Autodesk Fusion 360 part; units mm, degrees
(part 7 of 28)
  line L4044 (94.5774, 89.0483, -1.4859) -> (92.1274, 89.0483, -1.4859)
  line L4045 (92.1274, 89.0483, -1.4859) -> (92.1274, 92.0483, -1.4859)
  line L4046 (92.1274, 92.0483, -1.4859) -> (94.5774, 92.0483, -1.4859)
  line L4047 (94.5774, 92.0483, -1.4859) -> (94.5774, 89.0483, -1.4859)
  line L4048 (129.5024, 89.0483, -1.4859) -> (127.0524, 89.0483, -1.4859)
  line L4049 (127.0524, 89.0483, -1.4859) -> (127.0524, 92.0483, -1.4859)
  line L4050 (127.0524, 92.0483, -1.4859) -> (129.5024, 92.0483, -1.4859)
  line L4051 (129.5024, 92.0483, -1.4859) -> (129.5024, 89.0483, -1.4859)
  line L4052 (21.2483, 92.0145, -1.4859) -> (21.4312, 91.9551, -1.4859)
  line L4053 (21.4312, 91.9551, -1.4859) -> (21.6024, 91.8678, -1.4859)
  line L4054 (21.6024, 91.8678, -1.4859) -> (21.7579, 91.7548, -1.4859)
  line L4055 (21.7579, 91.7548, -1.4859) -> (21.8939, 91.6189, -1.4859)
  line L4056 (21.8939, 91.6189, -1.4859) -> (22.0069, 91.4634, -1.4859)
  line L4057 (22.0069, 91.4634, -1.4859) -> (22.0941, 91.2921, -1.4859)
  line L4058 (22.0941, 91.2921, -1.4859) -> (22.1535, 91.1093, -1.4859)
  line L4059 (22.1535, 91.1093, -1.4859) -> (22.1836, 90.9194, -1.4859)
  line L4060 (22.1836, 90.9194, -1.4859) -> (22.1874, 90.8233, -1.4859)
  line L4061 (22.1874, 90.8233, -1.4859) -> (22.1874, 90.2733, -1.4859)
  line L4062 (22.1874, 90.2733, -1.4859) -> (22.1836, 90.1772, -1.4859)
  line L4063 (22.1836, 90.1772, -1.4859) -> (22.1535, 89.9873, -1.4859)
  line L4064 (22.1535, 89.9873, -1.4859) -> (22.0941, 89.8045, -1.4859)
  line L4065 (22.0941, 89.8045, -1.4859) -> (22.0069, 89.6333, -1.4859)
  line L4066 (22.0069, 89.6333, -1.4859) -> (21.8939, 89.4777, -1.4859)
  line L4067 (21.8939, 89.4777, -1.4859) -> (21.7579, 89.3418, -1.4859)
  line L4068 (21.7579, 89.3418, -1.4859) -> (21.6024, 89.2288, -1.4859)
  line L4069 (21.6024, 89.2288, -1.4859) -> (21.4312, 89.1416, -1.4859)
  line L4070 (21.4312, 89.1416, -1.4859) -> (21.2483, 89.0822, -1.4859)
  line L4071 (21.2483, 89.0822, -1.4859) -> (21.0585, 89.0521, -1.4859)
  line L4072 (21.0585, 89.0521, -1.4859) -> (20.8663, 89.0521, -1.4859)
  line L4073 (20.8663, 89.0521, -1.4859) -> (20.6764, 89.0822, -1.4859)
  line L4074 (20.6764, 89.0822, -1.4859) -> (20.4936, 89.1416, -1.4859)
  line L4075 (20.4936, 89.1416, -1.4859) -> (20.3223, 89.2288, -1.4859)
  line L4076 (20.3223, 89.2288, -1.4859) -> (20.1668, 89.3418, -1.4859)
  line L4077 (20.1668, 89.3418, -1.4859) -> (20.0309, 89.4777, -1.4859)
  line L4078 (20.0309, 89.4777, -1.4859) -> (19.9179, 89.6333, -1.4859)
  line L4079 (19.9179, 89.6333, -1.4859) -> (19.8306, 89.8045, -1.4859)
  line L4080 (19.8306, 89.8045, -1.4859) -> (19.7712, 89.9873, -1.4859)
  line L4081 (19.7712, 89.9873, -1.4859) -> (19.7411, 90.1772, -1.4859)
  line L4082 (19.7411, 90.1772, -1.4859) -> (19.7374, 90.2733, -1.4859)
  line L4083 (19.7374, 90.2733, -1.4859) -> (19.7374, 90.8233, -1.4859)
  line L4084 (19.7374, 90.8233, -1.4859) -> (19.7411, 90.9194, -1.4859)
  line L4085 (19.7411, 90.9194, -1.4859) -> (19.7712, 91.1093, -1.4859)
  line L4086 (19.7712, 91.1093, -1.4859) -> (19.8306, 91.2921, -1.4859)
  line L4087 (19.8306, 91.2921, -1.4859) -> (19.9179, 91.4634, -1.4859)
  line L4088 (19.9179, 91.4634, -1.4859) -> (20.0309, 91.6189, -1.4859)
  line L4089 (20.0309, 91.6189, -1.4859) -> (20.1668, 91.7548, -1.4859)
  line L4090 (20.1668, 91.7548, -1.4859) -> (20.3223, 91.8678, -1.4859)
  line L4091 (20.3223, 91.8678, -1.4859) -> (20.4936, 91.9551, -1.4859)
  line L4092 (20.4936, 91.9551, -1.4859) -> (20.6764, 92.0145, -1.4859)
  line L4093 (20.6764, 92.0145, -1.4859) -> (20.8663, 92.0445, -1.4859)
  line L4094 (20.8663, 92.0445, -1.4859) -> (21.0585, 92.0445, -1.4859)
  line L4095 (21.0585, 92.0445, -1.4859) -> (21.2483, 92.0145, -1.4859)
  line L4096 (56.1733, 92.0145, -1.4859) -> (56.3562, 91.9551, -1.4859)
  line L4097 (56.3562, 91.9551, -1.4859) -> (56.5274, 91.8678, -1.4859)
  line L4098 (56.5274, 91.8678, -1.4859) -> (56.6829, 91.7548, -1.4859)
  line L4099 (56.6829, 91.7548, -1.4859) -> (56.8189, 91.6189, -1.4859)
  line L4100 (56.8189, 91.6189, -1.4859) -> (56.9319, 91.4634, -1.4859)
  line L4101 (56.9319, 91.4634, -1.4859) -> (57.0191, 91.2921, -1.4859)
  line L4102 (57.0191, 91.2921, -1.4859) -> (57.0785, 91.1093, -1.4859)
  line L4103 (57.0785, 91.1093, -1.4859) -> (57.1086, 90.9194, -1.4859)
  line L4104 (57.1086, 90.9194, -1.4859) -> (57.1124, 90.8233, -1.4859)
  line L4105 (57.1124, 90.8233, -1.4859) -> (57.1124, 90.2733, -1.4859)
  line L4106 (57.1124, 90.2733, -1.4859) -> (57.1086, 90.1772, -1.4859)
  line L4107 (57.1086, 90.1772, -1.4859) -> (57.0785, 89.9873, -1.4859)
  line L4108 (57.0785, 89.9873, -1.4859) -> (57.0191, 89.8045, -1.4859)
  line L4109 (57.0191, 89.8045, -1.4859) -> (56.9319, 89.6333, -1.4859)
  line L4110 (56.9319, 89.6333, -1.4859) -> (56.8189, 89.4777, -1.4859)
  line L4111 (56.8189, 89.4777, -1.4859) -> (56.6829, 89.3418, -1.4859)
  line L4112 (56.6829, 89.3418, -1.4859) -> (56.5274, 89.2288, -1.4859)
  line L4113 (56.5274, 89.2288, -1.4859) -> (56.3562, 89.1416, -1.4859)
  line L4114 (56.3562, 89.1416, -1.4859) -> (56.1733, 89.0822, -1.4859)
  line L4115 (56.1733, 89.0822, -1.4859) -> (55.9835, 89.0521, -1.4859)
  line L4116 (55.9835, 89.0521, -1.4859) -> (55.7913, 89.0521, -1.4859)
  line L4117 (55.7913, 89.0521, -1.4859) -> (55.6014, 89.0822, -1.4859)
  line L4118 (55.6014, 89.0822, -1.4859) -> (55.4186, 89.1416, -1.4859)
  line L4119 (55.4186, 89.1416, -1.4859) -> (55.2473, 89.2288, -1.4859)
  line L4120 (55.2473, 89.2288, -1.4859) -> (55.0918, 89.3418, -1.4859)
  line L4121 (55.0918, 89.3418, -1.4859) -> (54.9559, 89.4777, -1.4859)
  line L4122 (54.9559, 89.4777, -1.4859) -> (54.8429, 89.6333, -1.4859)
  line L4123 (54.8429, 89.6333, -1.4859) -> (54.7556, 89.8045, -1.4859)
  line L4124 (54.7556, 89.8045, -1.4859) -> (54.6962, 89.9873, -1.4859)
  line L4125 (54.6962, 89.9873, -1.4859) -> (54.6661, 90.1772, -1.4859)
  line L4126 (54.6661, 90.1772, -1.4859) -> (54.6624, 90.2733, -1.4859)
  line L4127 (54.6624, 90.2733, -1.4859) -> (54.6624, 90.8233, -1.4859)
  line L4128 (54.6624, 90.8233, -1.4859) -> (54.6661, 90.9194, -1.4859)
  line L4129 (54.6661, 90.9194, -1.4859) -> (54.6962, 91.1093, -1.4859)
  line L4130 (54.6962, 91.1093, -1.4859) -> (54.7556, 91.2921, -1.4859)
  line L4131 (54.7556, 91.2921, -1.4859) -> (54.8429, 91.4634, -1.4859)
  line L4132 (54.8429, 91.4634, -1.4859) -> (54.9559, 91.6189, -1.4859)
  line L4133 (54.9559, 91.6189, -1.4859) -> (55.0918, 91.7548, -1.4859)
  line L4134 (55.0918, 91.7548, -1.4859) -> (55.2473, 91.8678, -1.4859)
  line L4135 (55.2473, 91.8678, -1.4859) -> (55.4186, 91.9551, -1.4859)
  line L4136 (55.4186, 91.9551, -1.4859) -> (55.6014, 92.0145, -1.4859)
  line L4137 (55.6014, 92.0145, -1.4859) -> (55.7913, 92.0445, -1.4859)
  line L4138 (55.7913, 92.0445, -1.4859) -> (55.9835, 92.0445, -1.4859)
  line L4139 (55.9835, 92.0445, -1.4859) -> (56.1733, 92.0145, -1.4859)
  line L4140 (91.0983, 92.0145, -1.4859) -> (91.2812, 91.9551, -1.4859)
  line L4141 (91.2812, 91.9551, -1.4859) -> (91.4524, 91.8678, -1.4859)
  line L4142 (91.4524, 91.8678, -1.4859) -> (91.6079, 91.7548, -1.4859)
  line L4143 (91.6079, 91.7548, -1.4859) -> (91.7439, 91.6189, -1.4859)
  line L4144 (91.7439, 91.6189, -1.4859) -> (91.8569, 91.4634, -1.4859)
  line L4145 (91.8569, 91.4634, -1.4859) -> (91.9441, 91.2921, -1.4859)
  line L4146 (91.9441, 91.2921, -1.4859) -> (92.0035, 91.1093, -1.4859)
  line L4147 (92.0035, 91.1093, -1.4859) -> (92.0336, 90.9194, -1.4859)
  line L4148 (92.0336, 90.9194, -1.4859) -> (92.0374, 90.8233, -1.4859)
  line L4149 (92.0374, 90.8233, -1.4859) -> (92.0374, 90.2733, -1.4859)
  line L4150 (92.0374, 90.2733, -1.4859) -> (92.0336, 90.1772, -1.4859)
  line L4151 (92.0336, 90.1772, -1.4859) -> (92.0035, 89.9873, -1.4859)
  line L4152 (92.0035, 89.9873, -1.4859) -> (91.9441, 89.8045, -1.4859)
  line L4153 (91.9441, 89.8045, -1.4859) -> (91.8569, 89.6333, -1.4859)
  line L4154 (91.8569, 89.6333, -1.4859) -> (91.7439, 89.4777, -1.4859)
  line L4155 (91.7439, 89.4777, -1.4859) -> (91.6079, 89.3418, -1.4859)
  line L4156 (91.6079, 89.3418, -1.4859) -> (91.4524, 89.2288, -1.4859)
  line L4157 (91.4524, 89.2288, -1.4859) -> (91.2812, 89.1416, -1.4859)
  line L4158 (91.2812, 89.1416, -1.4859) -> (91.0983, 89.0822, -1.4859)
  line L4159 (91.0983, 89.0822, -1.4859) -> (90.9085, 89.0521, -1.4859)
  line L4160 (90.9085, 89.0521, -1.4859) -> (90.7163, 89.0521, -1.4859)
  line L4161 (90.7163, 89.0521, -1.4859) -> (90.5264, 89.0822, -1.4859)
  line L4162 (90.5264, 89.0822, -1.4859) -> (90.3436, 89.1416, -1.4859)
  line L4163 (90.3436, 89.1416, -1.4859) -> (90.1723, 89.2288, -1.4859)
  line L4164 (90.1723, 89.2288, -1.4859) -> (90.0168, 89.3418, -1.4859)
  line L4165 (90.0168, 89.3418, -1.4859) -> (89.8809, 89.4777, -1.4859)
  line L4166 (89.8809, 89.4777, -1.4859) -> (89.7679, 89.6333, -1.4859)
  line L4167 (89.7679, 89.6333, -1.4859) -> (89.6806, 89.8045, -1.4859)
  line L4168 (89.6806, 89.8045, -1.4859) -> (89.6212, 89.9873, -1.4859)
  line L4169 (89.6212, 89.9873, -1.4859) -> (89.5911, 90.1772, -1.4859)
  line L4170 (89.5911, 90.1772, -1.4859) -> (89.5874, 90.2733, -1.4859)
  line L4171 (89.5874, 90.2733, -1.4859) -> (89.5874, 90.8233, -1.4859)
  line L4172 (89.5874, 90.8233, -1.4859) -> (89.5911, 90.9194, -1.4859)
  line L4173 (89.5911, 90.9194, -1.4859) -> (89.6212, 91.1093, -1.4859)
  line L4174 (89.6212, 91.1093, -1.4859) -> (89.6806, 91.2921, -1.4859)
  line L4175 (89.6806, 91.2921, -1.4859) -> (89.7679, 91.4634, -1.4859)
  line L4176 (89.7679, 91.4634, -1.4859) -> (89.8809, 91.6189, -1.4859)
  line L4177 (89.8809, 91.6189, -1.4859) -> (90.0168, 91.7548, -1.4859)
  line L4178 (90.0168, 91.7548, -1.4859) -> (90.1723, 91.8678, -1.4859)
  line L4179 (90.1723, 91.8678, -1.4859) -> (90.3436, 91.9551, -1.4859)
  line L4180 (90.3436, 91.9551, -1.4859) -> (90.5264, 92.0145, -1.4859)
  line L4181 (90.5264, 92.0145, -1.4859) -> (90.7163, 92.0445, -1.4859)
  line L4182 (90.7163, 92.0445, -1.4859) -> (90.9085, 92.0445, -1.4859)
  line L4183 (90.9085, 92.0445, -1.4859) -> (91.0983, 92.0145, -1.4859)
  line L4184 (126.0233, 92.0145, -1.4859) -> (126.2062, 91.9551, -1.4859)
  line L4185 (126.2062, 91.9551, -1.4859) -> (126.3774, 91.8678, -1.4859)
  line L4186 (126.3774, 91.8678, -1.4859) -> (126.5329, 91.7548, -1.4859)
  line L4187 (126.5329, 91.7548, -1.4859) -> (126.6689, 91.6189, -1.4859)
  line L4188 (126.6689, 91.6189, -1.4859) -> (126.7819, 91.4634, -1.4859)
  line L4189 (126.7819, 91.4634, -1.4859) -> (126.8691, 91.2921, -1.4859)
  line L4190 (126.8691, 91.2921, -1.4859) -> (126.9285, 91.1093, -1.4859)
  line L4191 (126.9285, 91.1093, -1.4859) -> (126.9586, 90.9194, -1.4859)
  line L4192 (126.9586, 90.9194, -1.4859) -> (126.9624, 90.8233, -1.4859)
  line L4193 (126.9624, 90.8233, -1.4859) -> (126.9624, 90.2733, -1.4859)
  line L4194 (126.9624, 90.2733, -1.4859) -> (126.9586, 90.1772, -1.4859)
  line L4195 (126.9586, 90.1772, -1.4859) -> (126.9285, 89.9873, -1.4859)
  line L4196 (126.9285, 89.9873, -1.4859) -> (126.8691, 89.8045, -1.4859)
  line L4197 (126.8691, 89.8045, -1.4859) -> (126.7819, 89.6333, -1.4859)
  line L4198 (126.7819, 89.6333, -1.4859) -> (126.6689, 89.4777, -1.4859)
  line L4199 (126.6689, 89.4777, -1.4859) -> (126.5329, 89.3418, -1.4859)
  line L4200 (126.5329, 89.3418, -1.4859) -> (126.3774, 89.2288, -1.4859)
  line L4201 (126.3774, 89.2288, -1.4859) -> (126.2062, 89.1416, -1.4859)
  line L4202 (126.2062, 89.1416, -1.4859) -> (126.0233, 89.0822, -1.4859)
  line L4203 (126.0233, 89.0822, -1.4859) -> (125.8335, 89.0521, -1.4859)
  line L4204 (125.8335, 89.0521, -1.4859) -> (125.6413, 89.0521, -1.4859)
  line L4205 (125.6413, 89.0521, -1.4859) -> (125.4514, 89.0822, -1.4859)
  line L4206 (125.4514, 89.0822, -1.4859) -> (125.2686, 89.1416, -1.4859)
  line L4207 (125.2686, 89.1416, -1.4859) -> (125.0973, 89.2288, -1.4859)
  line L4208 (125.0973, 89.2288, -1.4859) -> (124.9418, 89.3418, -1.4859)
  line L4209 (124.9418, 89.3418, -1.4859) -> (124.8059, 89.4777, -1.4859)
  line L4210 (124.8059, 89.4777, -1.4859) -> (124.6929, 89.6333, -1.4859)
  line L4211 (124.6929, 89.6333, -1.4859) -> (124.6056, 89.8045, -1.4859)
  line L4212 (124.6056, 89.8045, -1.4859) -> (124.5462, 89.9873, -1.4859)
  line L4213 (124.5462, 89.9873, -1.4859) -> (124.5161, 90.1772, -1.4859)
  line L4214 (124.5161, 90.1772, -1.4859) -> (124.5124, 90.2733, -1.4859)
  line L4215 (124.5124, 90.2733, -1.4859) -> (124.5124, 90.8233, -1.4859)
  line L4216 (124.5124, 90.8233, -1.4859) -> (124.5161, 90.9194, -1.4859)
  line L4217 (124.5161, 90.9194, -1.4859) -> (124.5462, 91.1093, -1.4859)
  line L4218 (124.5462, 91.1093, -1.4859) -> (124.6056, 91.2921, -1.4859)
  line L4219 (124.6056, 91.2921, -1.4859) -> (124.6929, 91.4634, -1.4859)
  line L4220 (124.6929, 91.4634, -1.4859) -> (124.8059, 91.6189, -1.4859)
  line L4221 (124.8059, 91.6189, -1.4859) -> (124.9418, 91.7548, -1.4859)
  line L4222 (124.9418, 91.7548, -1.4859) -> (125.0973, 91.8678, -1.4859)
  line L4223 (125.0973, 91.8678, -1.4859) -> (125.2686, 91.9551, -1.4859)
  line L4224 (125.2686, 91.9551, -1.4859) -> (125.4514, 92.0145, -1.4859)
  line L4225 (125.4514, 92.0145, -1.4859) -> (125.6413, 92.0445, -1.4859)
  line L4226 (125.6413, 92.0445, -1.4859) -> (125.8335, 92.0445, -1.4859)
  line L4227 (125.8335, 92.0445, -1.4859) -> (126.0233, 92.0145, -1.4859)
  line L4228 (33.8345, 93.498, -1.4859) -> (34.021, 93.4374, -1.4859)
  line L4229 (34.021, 93.4374, -1.4859) -> (34.1958, 93.3483, -1.4859)
  line L4230 (34.1958, 93.3483, -1.4859) -> (34.3545, 93.233, -1.4859)
  line L4231 (34.3545, 93.233, -1.4859) -> (34.4932, 93.0943, -1.4859)
  line L4232 (34.4932, 93.0943, -1.4859) -> (34.6085, 92.9357, -1.4859)
  line L4233 (34.6085, 92.9357, -1.4859) -> (34.6975, 92.7609, -1.4859)
  line L4234 (34.6975, 92.7609, -1.4859) -> (34.7582, 92.5743, -1.4859)
  line L4235 (34.7582, 92.5743, -1.4859) -> (34.7888, 92.3806, -1.4859)
  line L4236 (34.7888, 92.3806, -1.4859) -> (34.7927, 92.2825, -1.4859)
  line L4237 (34.7927, 92.2825, -1.4859) -> (34.7927, 91.7825, -1.4859)
  line L4238 (34.7927, 91.7825, -1.4859) -> (34.7888, 91.6845, -1.4859)
  line L4239 (34.7888, 91.6845, -1.4859) -> (34.7582, 91.4907, -1.4859)
  line L4240 (34.7582, 91.4907, -1.4859) -> (34.6975, 91.3042, -1.4859)
  line L4241 (34.6975, 91.3042, -1.4859) -> (34.6085, 91.1294, -1.4859)
  line L4242 (34.6085, 91.1294, -1.4859) -> (34.4932, 90.9707, -1.4859)
  line L4243 (34.4932, 90.9707, -1.4859) -> (34.3545, 90.832, -1.4859)
  line L4244 (34.3545, 90.832, -1.4859) -> (34.1958, 90.7167, -1.4859)
  line L4245 (34.1958, 90.7167, -1.4859) -> (34.021, 90.6277, -1.4859)
  line L4246 (34.021, 90.6277, -1.4859) -> (33.8345, 90.5671, -1.4859)
  line L4247 (33.8345, 90.5671, -1.4859) -> (33.6408, 90.5364, -1.4859)
  line L4248 (33.6408, 90.5364, -1.4859) -> (33.4446, 90.5364, -1.4859)
  line L4249 (33.4446, 90.5364, -1.4859) -> (33.2509, 90.5671, -1.4859)
  line L4250 (33.2509, 90.5671, -1.4859) -> (33.0643, 90.6277, -1.4859)
  line L4251 (33.0643, 90.6277, -1.4859) -> (32.8896, 90.7167, -1.4859)
  line L4252 (32.8896, 90.7167, -1.4859) -> (32.7309, 90.832, -1.4859)
  line L4253 (32.7309, 90.832, -1.4859) -> (32.5922, 90.9707, -1.4859)
  line L4254 (32.5922, 90.9707, -1.4859) -> (32.4769, 91.1294, -1.4859)
  line L4255 (32.4769, 91.1294, -1.4859) -> (32.3878, 91.3042, -1.4859)
  line L4256 (32.3878, 91.3042, -1.4859) -> (32.3272, 91.4907, -1.4859)
  line L4257 (32.3272, 91.4907, -1.4859) -> (32.2965, 91.6845, -1.4859)
  line L4258 (32.2965, 91.6845, -1.4859) -> (32.2927, 91.7825, -1.4859)
  line L4259 (32.2927, 91.7825, -1.4859) -> (32.2927, 92.2825, -1.4859)
  line L4260 (32.2927, 92.2825, -1.4859) -> (32.2965, 92.3806, -1.4859)
  line L4261 (32.2965, 92.3806, -1.4859) -> (32.3272, 92.5743, -1.4859)
  line L4262 (32.3272, 92.5743, -1.4859) -> (32.3878, 92.7609, -1.4859)
  line L4263 (32.3878, 92.7609, -1.4859) -> (32.4769, 92.9357, -1.4859)
  line L4264 (32.4769, 92.9357, -1.4859) -> (32.5922, 93.0943, -1.4859)
  line L4265 (32.5922, 93.0943, -1.4859) -> (32.7309, 93.233, -1.4859)
  line L4266 (32.7309, 93.233, -1.4859) -> (32.8896, 93.3483, -1.4859)
  line L4267 (32.8896, 93.3483, -1.4859) -> (33.0643, 93.4374, -1.4859)
  line L4268 (33.0643, 93.4374, -1.4859) -> (33.2509, 93.498, -1.4859)
  line L4269 (33.2509, 93.498, -1.4859) -> (33.4446, 93.5287, -1.4859)
  line L4270 (33.4446, 93.5287, -1.4859) -> (33.6408, 93.5287, -1.4859)
  line L4271 (33.6408, 93.5287, -1.4859) -> (33.8345, 93.498, -1.4859)
  line L4272 (68.7595, 93.498, -1.4859) -> (68.946, 93.4374, -1.4859)
  line L4273 (68.946, 93.4374, -1.4859) -> (69.1208, 93.3483, -1.4859)
  line L4274 (69.1208, 93.3483, -1.4859) -> (69.2795, 93.233, -1.4859)
  line L4275 (69.2795, 93.233, -1.4859) -> (69.4182, 93.0943, -1.4859)
  line L4276 (69.4182, 93.0943, -1.4859) -> (69.5335, 92.9357, -1.4859)
  line L4277 (69.5335, 92.9357, -1.4859) -> (69.6225, 92.7609, -1.4859)
  line L4278 (69.6225, 92.7609, -1.4859) -> (69.6832, 92.5743, -1.4859)
  line L4279 (69.6832, 92.5743, -1.4859) -> (69.7138, 92.3806, -1.4859)
  line L4280 (69.7138, 92.3806, -1.4859) -> (69.7177, 92.2825, -1.4859)
  line L4281 (69.7177, 92.2825, -1.4859) -> (69.7177, 91.7825, -1.4859)
  line L4282 (69.7177, 91.7825, -1.4859) -> (69.7138, 91.6845, -1.4859)
  line L4283 (69.7138, 91.6845, -1.4859) -> (69.6832, 91.4907, -1.4859)
  line L4284 (69.6832, 91.4907, -1.4859) -> (69.6225, 91.3042, -1.4859)
  line L4285 (69.6225, 91.3042, -1.4859) -> (69.5335, 91.1294, -1.4859)
  line L4286 (69.5335, 91.1294, -1.4859) -> (69.4182, 90.9707, -1.4859)
  line L4287 (69.4182, 90.9707, -1.4859) -> (69.2795, 90.832, -1.4859)
  line L4288 (69.2795, 90.832, -1.4859) -> (69.1208, 90.7167, -1.4859)
  line L4289 (69.1208, 90.7167, -1.4859) -> (68.946, 90.6277, -1.4859)
  line L4290 (68.946, 90.6277, -1.4859) -> (68.7595, 90.5671, -1.4859)
  line L4291 (68.7595, 90.5671, -1.4859) -> (68.5658, 90.5364, -1.4859)
  line L4292 (68.5658, 90.5364, -1.4859) -> (68.3696, 90.5364, -1.4859)
  line L4293 (68.3696, 90.5364, -1.4859) -> (68.1759, 90.5671, -1.4859)
  line L4294 (68.1759, 90.5671, -1.4859) -> (67.9893, 90.6277, -1.4859)
  line L4295 (67.9893, 90.6277, -1.4859) -> (67.8146, 90.7167, -1.4859)
  line L4296 (67.8146, 90.7167, -1.4859) -> (67.6559, 90.832, -1.4859)
  line L4297 (67.6559, 90.832, -1.4859) -> (67.5172, 90.9707, -1.4859)
  line L4298 (67.5172, 90.9707, -1.4859) -> (67.4019, 91.1294, -1.4859)
  line L4299 (67.4019, 91.1294, -1.4859) -> (67.3128, 91.3042, -1.4859)
  line L4300 (67.3128, 91.3042, -1.4859) -> (67.2522, 91.4907, -1.4859)
  line L4301 (67.2522, 91.4907, -1.4859) -> (67.2215, 91.6845, -1.4859)
  line L4302 (67.2215, 91.6845, -1.4859) -> (67.2177, 91.7825, -1.4859)
  line L4303 (67.2177, 91.7825, -1.4859) -> (67.2177, 92.2825, -1.4859)
  line L4304 (67.2177, 92.2825, -1.4859) -> (67.2215, 92.3806, -1.4859)
  line L4305 (67.2215, 92.3806, -1.4859) -> (67.2522, 92.5743, -1.4859)
  line L4306 (67.2522, 92.5743, -1.4859) -> (67.3128, 92.7609, -1.4859)
  line L4307 (67.3128, 92.7609, -1.4859) -> (67.4019, 92.9357, -1.4859)
  line L4308 (67.4019, 92.9357, -1.4859) -> (67.5172, 93.0943, -1.4859)
  line L4309 (67.5172, 93.0943, -1.4859) -> (67.6559, 93.233, -1.4859)
  line L4310 (67.6559, 93.233, -1.4859) -> (67.8146, 93.3483, -1.4859)
  line L4311 (67.8146, 93.3483, -1.4859) -> (67.9893, 93.4374, -1.4859)
  line L4312 (67.9893, 93.4374, -1.4859) -> (68.1759, 93.498, -1.4859)
  line L4313 (68.1759, 93.498, -1.4859) -> (68.3696, 93.5287, -1.4859)
  line L4314 (68.3696, 93.5287, -1.4859) -> (68.5658, 93.5287, -1.4859)
  line L4315 (68.5658, 93.5287, -1.4859) -> (68.7595, 93.498, -1.4859)
  line L4316 (103.6845, 93.498, -1.4859) -> (103.871, 93.4374, -1.4859)
  line L4317 (103.871, 93.4374, -1.4859) -> (104.0458, 93.3483, -1.4859)
  line L4318 (104.0458, 93.3483, -1.4859) -> (104.2045, 93.233, -1.4859)
  line L4319 (104.2045, 93.233, -1.4859) -> (104.3432, 93.0943, -1.4859)
  line L4320 (104.3432, 93.0943, -1.4859) -> (104.4585, 92.9357, -1.4859)
  line L4321 (104.4585, 92.9357, -1.4859) -> (104.5475, 92.7609, -1.4859)
  line L4322 (104.5475, 92.7609, -1.4859) -> (104.6082, 92.5743, -1.4859)
  line L4323 (104.6082, 92.5743, -1.4859) -> (104.6388, 92.3806, -1.4859)
  line L4324 (104.6388, 92.3806, -1.4859) -> (104.6427, 92.2825, -1.4859)
  line L4325 (104.6427, 92.2825, -1.4859) -> (104.6427, 91.7825, -1.4859)
  line L4326 (104.6427, 91.7825, -1.4859) -> (104.6388, 91.6845, -1.4859)
  line L4327 (104.6388, 91.6845, -1.4859) -> (104.6082, 91.4907, -1.4859)
  line L4328 (104.6082, 91.4907, -1.4859) -> (104.5475, 91.3042, -1.4859)
  line L4329 (104.5475, 91.3042, -1.4859) -> (104.4585, 91.1294, -1.4859)
  line L4330 (104.4585, 91.1294, -1.4859) -> (104.3432, 90.9707, -1.4859)
  line L4331 (104.3432, 90.9707, -1.4859) -> (104.2045, 90.832, -1.4859)
  line L4332 (104.2045, 90.832, -1.4859) -> (104.0458, 90.7167, -1.4859)
  line L4333 (104.0458, 90.7167, -1.4859) -> (103.871, 90.6277, -1.4859)
  line L4334 (103.871, 90.6277, -1.4859) -> (103.6845, 90.5671, -1.4859)
  line L4335 (103.6845, 90.5671, -1.4859) -> (103.4908, 90.5364, -1.4859)
  line L4336 (103.4908, 90.5364, -1.4859) -> (103.2946, 90.5364, -1.4859)
  line L4337 (103.2946, 90.5364, -1.4859) -> (103.1009, 90.5671, -1.4859)
  line L4338 (103.1009, 90.5671, -1.4859) -> (102.9143, 90.6277, -1.4859)
  line L4339 (102.9143, 90.6277, -1.4859) -> (102.7396, 90.7167, -1.4859)
  line L4340 (102.7396, 90.7167, -1.4859) -> (102.5809, 90.832, -1.4859)
  line L4341 (102.5809, 90.832, -1.4859) -> (102.4422, 90.9707, -1.4859)
  line L4342 (102.4422, 90.9707, -1.4859) -> (102.3269, 91.1294, -1.4859)
  line L4343 (102.3269, 91.1294, -1.4859) -> (102.2378, 91.3042, -1.4859)
  line L4344 (102.2378, 91.3042, -1.4859) -> (102.1772, 91.4907, -1.4859)
  line L4345 (102.1772, 91.4907, -1.4859) -> (102.1465, 91.6845, -1.4859)
  line L4346 (102.1465, 91.6845, -1.4859) -> (102.1427, 91.7825, -1.4859)
  line L4347 (102.1427, 91.7825, -1.4859) -> (102.1427, 92.2825, -1.4859)
  line L4348 (102.1427, 92.2825, -1.4859) -> (102.1465, 92.3806, -1.4859)
  line L4349 (102.1465, 92.3806, -1.4859) -> (102.1772, 92.5743, -1.4859)
  line L4350 (102.1772, 92.5743, -1.4859) -> (102.2378, 92.7609, -1.4859)
  line L4351 (102.2378, 92.7609, -1.4859) -> (102.3269, 92.9357, -1.4859)
  line L4352 (102.3269, 92.9357, -1.4859) -> (102.4422, 93.0943, -1.4859)
  line L4353 (102.4422, 93.0943, -1.4859) -> (102.5809, 93.233, -1.4859)
  line L4354 (102.5809, 93.233, -1.4859) -> (102.7396, 93.3483, -1.4859)
  line L4355 (102.7396, 93.3483, -1.4859) -> (102.9143, 93.4374, -1.4859)
  line L4356 (102.9143, 93.4374, -1.4859) -> (103.1009, 93.498, -1.4859)
  line L4357 (103.1009, 93.498, -1.4859) -> (103.2946, 93.5287, -1.4859)
  line L4358 (103.2946, 93.5287, -1.4859) -> (103.4908, 93.5287, -1.4859)
  line L4359 (103.4908, 93.5287, -1.4859) -> (103.6845, 93.498, -1.4859)
  line L4360 (138.6095, 93.498, -1.4859) -> (138.796, 93.4374, -1.4859)
  line L4361 (138.796, 93.4374, -1.4859) -> (138.9708, 93.3483, -1.4859)
  line L4362 (138.9708, 93.3483, -1.4859) -> (139.1295, 93.233, -1.4859)
  line L4363 (139.1295, 93.233, -1.4859) -> (139.2682, 93.0943, -1.4859)
  line L4364 (139.2682, 93.0943, -1.4859) -> (139.3835, 92.9357, -1.4859)
  line L4365 (139.3835, 92.9357, -1.4859) -> (139.4725, 92.7609, -1.4859)
  line L4366 (139.4725, 92.7609, -1.4859) -> (139.5332, 92.5743, -1.4859)
  line L4367 (139.5332, 92.5743, -1.4859) -> (139.5638, 92.3806, -1.4859)
  line L4368 (139.5638, 92.3806, -1.4859) -> (139.5677, 92.2825, -1.4859)
  line L4369 (139.5677, 92.2825, -1.4859) -> (139.5677, 91.7825, -1.4859)
  line L4370 (139.5677, 91.7825, -1.4859) -> (139.5638, 91.6845, -1.4859)
  line L4371 (139.5638, 91.6845, -1.4859) -> (139.5332, 91.4907, -1.4859)
  line L4372 (139.5332, 91.4907, -1.4859) -> (139.4725, 91.3042, -1.4859)
  line L4373 (139.4725, 91.3042, -1.4859) -> (139.3835, 91.1294, -1.4859)
  line L4374 (139.3835, 91.1294, -1.4859) -> (139.2682, 90.9707, -1.4859)
  line L4375 (139.2682, 90.9707, -1.4859) -> (139.1295, 90.832, -1.4859)
  line L4376 (139.1295, 90.832, -1.4859) -> (138.9708, 90.7167, -1.4859)
  line L4377 (138.9708, 90.7167, -1.4859) -> (138.796, 90.6277, -1.4859)
  line L4378 (138.796, 90.6277, -1.4859) -> (138.6095, 90.5671, -1.4859)
  line L4379 (138.6095, 90.5671, -1.4859) -> (138.4158, 90.5364, -1.4859)
  line L4380 (138.4158, 90.5364, -1.4859) -> (138.2196, 90.5364, -1.4859)
  line L4381 (138.2196, 90.5364, -1.4859) -> (138.0259, 90.5671, -1.4859)
  line L4382 (138.0259, 90.5671, -1.4859) -> (137.8393, 90.6277, -1.4859)
  line L4383 (137.8393, 90.6277, -1.4859) -> (137.6646, 90.7167, -1.4859)
  line L4384 (137.6646, 90.7167, -1.4859) -> (137.5059, 90.832, -1.4859)
  line L4385 (137.5059, 90.832, -1.4859) -> (137.3672, 90.9707, -1.4859)
  line L4386 (137.3672, 90.9707, -1.4859) -> (137.2519, 91.1294, -1.4859)
  line L4387 (137.2519, 91.1294, -1.4859) -> (137.1628, 91.3042, -1.4859)
  line L4388 (137.1628, 91.3042, -1.4859) -> (137.1022, 91.4907, -1.4859)
  line L4389 (137.1022, 91.4907, -1.4859) -> (137.0715, 91.6845, -1.4859)
  line L4390 (137.0715, 91.6845, -1.4859) -> (137.0677, 91.7825, -1.4859)
  line L4391 (137.0677, 91.7825, -1.4859) -> (137.0677, 92.2825, -1.4859)
  line L4392 (137.0677, 92.2825, -1.4859) -> (137.0715, 92.3806, -1.4859)
  line L4393 (137.0715, 92.3806, -1.4859) -> (137.1022, 92.5743, -1.4859)
  line L4394 (137.1022, 92.5743, -1.4859) -> (137.1628, 92.7609, -1.4859)
  line L4395 (137.1628, 92.7609, -1.4859) -> (137.2519, 92.9357, -1.4859)
  line L4396 (137.2519, 92.9357, -1.4859) -> (137.3672, 93.0943, -1.4859)
  line L4397 (137.3672, 93.0943, -1.4859) -> (137.5059, 93.233, -1.4859)
  line L4398 (137.5059, 93.233, -1.4859) -> (137.6646, 93.3483, -1.4859)
  line L4399 (137.6646, 93.3483, -1.4859) -> (137.8393, 93.4374, -1.4859)
  line L4400 (137.8393, 93.4374, -1.4859) -> (138.0259, 93.498, -1.4859)
  line L4401 (138.0259, 93.498, -1.4859) -> (138.2196, 93.5287, -1.4859)
  line L4402 (138.2196, 93.5287, -1.4859) -> (138.4158, 93.5287, -1.4859)
  line L4403 (138.4158, 93.5287, -1.4859) -> (138.6095, 93.498, -1.4859)
  line L4404 (0.0231, 6.9946) -> (0.025, 6.985)
  line L4405 (0.025, 6.985) -> (0.025, 0.025)
  line L4406 (0.025, 0.025) -> (7.62, 0.025)
  line L4407 (7.62, 0.025) -> (7.6296, 0.0231)
  line L4408 (7.6296, 0.0231) -> (7.6431, 0.0096)
  line L4409 (7.6431, 0.0096) -> (7.6431, -0.0096)
  line L4410 (7.6431, -0.0096) -> (7.6296, -0.0231)
  line L4411 (7.6296, -0.0231) -> (7.62, -0.025)
  line L4412 (7.62, -0.025) -> (0.025, -0.025)
  line L4413 (0.025, -0.025) -> (0.025, -5.08)
  line L4414 (0.025, -5.08) -> (0.0231, -5.0896)
  line L4415 (0.0231, -5.0896) -> (0.0096, -5.1031)
  line L4416 (0.0096, -5.1031) -> (-0.0096, -5.1031)
  line L4417 (-0.0096, -5.1031) -> (-0.0231, -5.0896)
  line L4418 (-0.0231, -5.0896) -> (-0.025, -5.08)
  line L4419 (-0.025, -5.08) -> (-0.025, -0.025)
  line L4420 (-0.025, -0.025) -> (-5.08, -0.025)
  line L4421 (-5.08, -0.025) -> (-5.0896, -0.0231)
  line L4422 (-5.0896, -0.0231) -> (-5.1031, -0.0096)
  line L4423 (-5.1031, -0.0096) -> (-5.1031, 0.0096)
  line L4424 (-5.1031, 0.0096) -> (-5.0896, 0.0231)
  line L4425 (-5.0896, 0.0231) -> (-5.08, 0.025)
  line L4426 (-5.08, 0.025) -> (-0.025, 0.025)
  line L4427 (-0.025, 0.025) -> (-0.025, 6.985)
  line L4428 (-0.025, 6.985) -> (-0.0231, 6.9946)
  line L4429 (-0.0231, 6.9946) -> (-0.0096, 7.0081)
  line L4430 (-0.0096, 7.0081) -> (0.0096, 7.0081)
  line L4431 (0.0096, 7.0081) -> (0.0231, 6.9946)
  line L4432 (66.015, 36.83, -1.4859) -> (66.0246, 36.8281, -1.4859)
  line L4433 (66.0246, 36.8281, -1.4859) -> (66.0381, 36.8146, -1.4859)
  line L4434 (66.0381, 36.8146, -1.4859) -> (66.04, 36.805, -1.4859)
  line L4435 (66.04, 36.805, -1.4859) -> (66.04, 5.055, -1.4859)
  line L4436 (66.04, 5.055, -1.4859) -> (66.0381, 5.0454, -1.4859)
  line L4437 (66.0381, 5.0454, -1.4859) -> (66.0246, 5.0319, -1.4859)
  line L4438 (66.0246, 5.0319, -1.4859) -> (66.015, 5.03, -1.4859)
  line L4439 (66.015, 5.03, -1.4859) -> (8.23, 5.03, -1.4859)
  line L4440 (8.23, 5.03, -1.4859) -> (8.2204, 5.0319, -1.4859)
  line L4441 (8.2204, 5.0319, -1.4859) -> (8.2069, 5.0454, -1.4859)
  line L4442 (8.2069, 5.0454, -1.4859) -> (8.205, 5.055, -1.4859)
  line L4443 (8.205, 5.055, -1.4859) -> (8.205, 36.805, -1.4859)
  line L4444 (8.205, 36.805, -1.4859) -> (8.2069, 36.8146, -1.4859)
  line L4445 (8.2069, 36.8146, -1.4859) -> (8.2204, 36.8281, -1.4859)
  line L4446 (8.2204, 36.8281, -1.4859) -> (8.23, 36.83, -1.4859)
  line L4447 (8.23, 36.83, -1.4859) -> (66.015, 36.83, -1.4859)
  line L4448 (8.255, 36.78, -1.4859) -> (8.255, 5.08, -1.4859)
  line L4449 (8.255, 5.08, -1.4859) -> (65.99, 5.08, -1.4859)
  line L4450 (65.99, 5.08, -1.4859) -> (65.99, 36.78, -1.4859)
  line L4451 (65.99, 36.78, -1.4859) -> (62.84, 36.78, -1.4859)
  line L4452 (62.84, 36.78, -1.4859) -> (8.255, 36.78, -1.4859)
  line L4453 (126.975, 36.83, -1.4859) -> (126.9846, 36.8281, -1.4859)
  line L4454 (126.9846, 36.8281, -1.4859) -> (126.9981, 36.8146, -1.4859)
  line L4455 (126.9981, 36.8146, -1.4859) -> (127, 36.805, -1.4859)
  line L4456 (127, 36.805, -1.4859) -> (127, 5.055, -1.4859)
  line L4457 (127, 5.055, -1.4859) -> (126.9981, 5.0454, -1.4859)
  line L4458 (126.9981, 5.0454, -1.4859) -> (126.9846, 5.0319, -1.4859)
  line L4459 (126.9846, 5.0319, -1.4859) -> (126.975, 5.03, -1.4859)
  line L4460 (126.975, 5.03, -1.4859) -> (69.19, 5.03, -1.4859)
  line L4461 (69.19, 5.03, -1.4859) -> (69.1804, 5.0319, -1.4859)
  line L4462 (69.1804, 5.0319, -1.4859) -> (69.1669, 5.0454, -1.4859)
  line L4463 (69.1669, 5.0454, -1.4859) -> (69.165, 5.055, -1.4859)
  line L4464 (69.165, 5.055, -1.4859) -> (69.165, 36.805, -1.4859)
  line L4465 (69.165, 36.805, -1.4859) -> (69.1669, 36.8146, -1.4859)
  line L4466 (69.1669, 36.8146, -1.4859) -> (69.1804, 36.8281, -1.4859)
  line L4467 (69.1804, 36.8281, -1.4859) -> (69.19, 36.83, -1.4859)
  line L4468 (69.19, 36.83, -1.4859) -> (126.975, 36.83, -1.4859)
  line L4469 (69.215, 36.78, -1.4859) -> (69.215, 5.08, -1.4859)
  line L4470 (69.215, 5.08, -1.4859) -> (126.95, 5.08, -1.4859)
  line L4471 (126.95, 5.08, -1.4859) -> (126.95, 36.78, -1.4859)
  line L4472 (126.95, 36.78, -1.4859) -> (123.8, 36.78, -1.4859)
  line L4473 (123.8, 36.78, -1.4859) -> (69.215, 36.78, -1.4859)
  line L4474 (39.98, 97.79, -1.4859) -> (43.155, 97.79, -1.4859)
  line L4475 (43.155, 97.79, -1.4859) -> (74.905, 97.79, -1.4859)
  line L4476 (74.905, 97.79, -1.4859) -> (74.9146, 97.7881, -1.4859)
  line L4477 (74.9146, 97.7881, -1.4859) -> (74.9281, 97.7746, -1.4859)
  line L4478 (74.9281, 97.7746, -1.4859) -> (74.93, 97.765, -1.4859)
  line L4479 (74.93, 97.765, -1.4859) -> (74.93, 39.98, -1.4859)
  line L4480 (74.93, 39.98, -1.4859) -> (74.9281, 39.9704, -1.4859)
  line L4481 (74.9281, 39.9704, -1.4859) -> (74.9146, 39.9569, -1.4859)
  line L4482 (74.9146, 39.9569, -1.4859) -> (74.905, 39.955, -1.4859)
  line L4483 (74.905, 39.955, -1.4859) -> (43.155, 39.955, -1.4859)
  line L4484 (43.155, 39.955, -1.4859) -> (43.1454, 39.9569, -1.4859)
  line L4485 (43.1454, 39.9569, -1.4859) -> (43.1319, 39.9704, -1.4859)
  line L4486 (43.1319, 39.9704, -1.4859) -> (43.13, 39.98, -1.4859)
  line L4487 (43.13, 39.98, -1.4859) -> (43.13, 97.74, -1.4859)
  line L4488 (43.13, 97.74, -1.4859) -> (40.005, 97.74, -1.4859)
  line L4489 (40.005, 97.74, -1.4859) -> (40.005, 39.98, -1.4859)
  line L4490 (40.005, 39.98, -1.4859) -> (40.0031, 39.9704, -1.4859)
  line L4491 (40.0031, 39.9704, -1.4859) -> (39.9896, 39.9569, -1.4859)
  line L4492 (39.9896, 39.9569, -1.4859) -> (39.98, 39.955, -1.4859)
  line L4493 (39.98, 39.955, -1.4859) -> (8.23, 39.955, -1.4859)
  line L4494 (8.23, 39.955, -1.4859) -> (8.2204, 39.9569, -1.4859)
  line L4495 (8.2204, 39.9569, -1.4859) -> (8.2069, 39.9704, -1.4859)
  line L4496 (8.2069, 39.9704, -1.4859) -> (8.205, 39.98, -1.4859)
  line L4497 (8.205, 39.98, -1.4859) -> (8.205, 97.765, -1.4859)
  line L4498 (8.205, 97.765, -1.4859) -> (8.2069, 97.7746, -1.4859)
  line L4499 (8.2069, 97.7746, -1.4859) -> (8.2204, 97.7881, -1.4859)
  line L4500 (8.2204, 97.7881, -1.4859) -> (8.23, 97.79, -1.4859)
  line L4501 (8.23, 97.79, -1.4859) -> (39.98, 97.79, -1.4859)
  line L4502 (43.18, 97.74, -1.4859) -> (43.18, 40.005, -1.4859)
  line L4503 (43.18, 40.005, -1.4859) -> (74.88, 40.005, -1.4859)
  line L4504 (74.88, 40.005, -1.4859) -> (74.88, 97.74, -1.4859)
  line L4505 (74.88, 97.74, -1.4859) -> (43.18, 97.74, -1.4859)
  line L4506 (8.255, 97.74, -1.4859) -> (8.255, 40.005, -1.4859)
  line L4507 (8.255, 40.005, -1.4859) -> (39.955, 40.005, -1.4859)
  line L4508 (39.955, 40.005, -1.4859) -> (39.955, 97.74, -1.4859)
  line L4509 (39.955, 97.74, -1.4859) -> (8.255, 97.74, -1.4859)
  line L4510 (109.8396, 97.7881, -1.4859) -> (109.8531, 97.7746, -1.4859)
  line L4511 (109.8531, 97.7746, -1.4859) -> (109.855, 97.765, -1.4859)
  line L4512 (109.855, 97.765, -1.4859) -> (109.855, 39.98, -1.4859)
  line L4513 (109.855, 39.98, -1.4859) -> (109.8531, 39.9704, -1.4859)
  line L4514 (109.8531, 39.9704, -1.4859) -> (109.8396, 39.9569, -1.4859)
  line L4515 (109.8396, 39.9569, -1.4859) -> (109.83, 39.955, -1.4859)
  line L4516 (109.83, 39.955, -1.4859) -> (78.08, 39.955, -1.4859)
  line L4517 (78.08, 39.955, -1.4859) -> (78.0704, 39.9569, -1.4859)
  line L4518 (78.0704, 39.9569, -1.4859) -> (78.0569, 39.9704, -1.4859)
  line L4519 (78.0569, 39.9704, -1.4859) -> (78.055, 39.98, -1.4859)
  line L4520 (78.055, 39.98, -1.4859) -> (78.055, 97.765, -1.4859)
  line L4521 (78.055, 97.765, -1.4859) -> (78.0569, 97.7746, -1.4859)
  line L4522 (78.0569, 97.7746, -1.4859) -> (78.0704, 97.7881, -1.4859)
  line L4523 (78.0704, 97.7881, -1.4859) -> (78.08, 97.79, -1.4859)
  line L4524 (78.08, 97.79, -1.4859) -> (109.83, 97.79, -1.4859)
  line L4525 (109.83, 97.79, -1.4859) -> (109.8396, 97.7881, -1.4859)
  line L4526 (78.105, 97.74, -1.4859) -> (78.105, 40.005, -1.4859)
  line L4527 (78.105, 40.005, -1.4859) -> (109.805, 40.005, -1.4859)
  line L4528 (109.805, 40.005, -1.4859) -> (109.805, 97.74, -1.4859)
  line L4529 (109.805, 97.74, -1.4859) -> (78.105, 97.74, -1.4859)
  line L4530 (144.7646, 97.7881, -1.4859) -> (144.7781, 97.7746, -1.4859)
  line L4531 (144.7781, 97.7746, -1.4859) -> (144.78, 97.765, -1.4859)
  line L4532 (144.78, 97.765, -1.4859) -> (144.78, 39.98, -1.4859)
  line L4533 (144.78, 39.98, -1.4859) -> (144.7781, 39.9704, -1.4859)
  line L4534 (144.7781, 39.9704, -1.4859) -> (144.7646, 39.9569, -1.4859)
  line L4535 (144.7646, 39.9569, -1.4859) -> (144.755, 39.955, -1.4859)
  line L4536 (144.755, 39.955, -1.4859) -> (113.005, 39.955, -1.4859)
  line L4537 (113.005, 39.955, -1.4859) -> (112.9954, 39.9569, -1.4859)
  line L4538 (112.9954, 39.9569, -1.4859) -> (112.9819, 39.9704, -1.4859)
  line L4539 (112.9819, 39.9704, -1.4859) -> (112.98, 39.98, -1.4859)
  line L4540 (112.98, 39.98, -1.4859) -> (112.98, 97.765, -1.4859)
  line L4541 (112.98, 97.765, -1.4859) -> (112.9819, 97.7746, -1.4859)
  line L4542 (112.9819, 97.7746, -1.4859) -> (112.9954, 97.7881, -1.4859)
  line L4543 (112.9954, 97.7881, -1.4859) -> (113.005, 97.79, -1.4859)
  line L4544 (113.005, 97.79, -1.4859) -> (144.755, 97.79, -1.4859)
  line L4545 (144.755, 97.79, -1.4859) -> (144.7646, 97.7881, -1.4859)
  line L4546 (113.03, 97.74, -1.4859) -> (113.03, 40.005, -1.4859)
  line L4547 (113.03, 40.005, -1.4859) -> (144.73, 40.005, -1.4859)
  line L4548 (144.73, 40.005, -1.4859) -> (144.73, 97.74, -1.4859)
  line L4549 (144.73, 97.74, -1.4859) -> (113.03, 97.74, -1.4859)